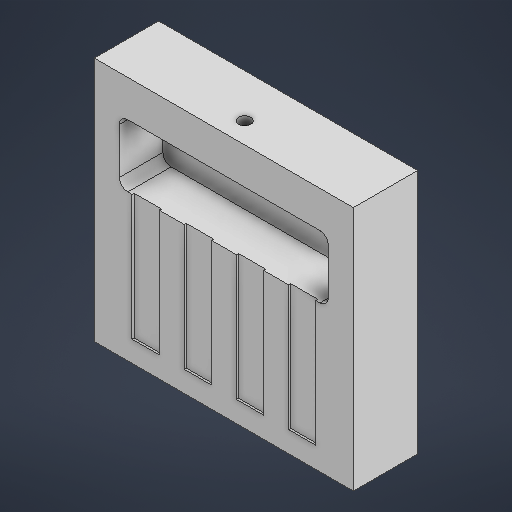
# Autodesk Inventor part: coffin_4Q_bottom
Saved by Autodesk Inventor 2026.2 (Build 302298010, 298A)
## iProperties
Created: 2026-11-02
Part Number: coffin_4Q_bottom
Material: Generic
Document SubType Name: Modeling
Designer: epm114
Mass: 47.8806 g
Surface Area: 125.077 cm^2
Volume: 47.8806 cm^3
Density: 1 g/cm^3
Appearance: Default
Author: epm114
Autodesk Inventor part; units mm, degrees
ref_plane "YZ Plane" through (0, 0, 0) normal (1, 0, 0) x (0, 1, 0)
ref_plane "XY Plane" through (0, 0, 0) normal (0, 0, 1) x (1, 0, 0)
sketch "Block_sketch" plane through (0, 0, 0) normal (0, 0, 1) x (1, 0, 0)
  line L0 (-31, -42.5) -> (31, -42.5)
  line L1 (31, -42.5) -> (31, 16.25)
  line L2 (31, 16.25) -> (-31, 16.25)
  line L3 (-31, 16.25) -> (-31, -42.5)
  point P0 (0, 0)
  dimension "d0" = 62
  dimension "d1" = 58.75
  dimension "d2" = 31
  dimension "d3" = 42.5
  constraints: 8 end point, 2 horizontal, 2 vertical
  measures "d0" distance between parallel lines of L3 L1
  measures "d1" distance between parallel lines of L0 L2
  measures "d2" horizontal distance of point (0, 0) L0.start
  measures "d3" vertical distance of point (0, 0) L0.start
extrude "Block" add sketch "Block_sketch" against normal blind 15.4
sketch "Cavity_sketch" plane through (0, 0, 0) normal (0, 0, 1) x (1, 0, 0)
  arc A0 (-25, -5.5) -> (-23, -7.5) centre (-23, -5.5) ccw
  arc A1 (23, -7.5) -> (25, -5.5) centre (23, -5.5) ccw
  arc A2 (25, 5.5) -> (23, 7.5) centre (23, 5.5) ccw
  arc A3 (-23, 7.5) -> (-25, 5.5) centre (-23, 5.5) ccw
  line L0 (-23, -7.5) -> (23, -7.5)
  line L1 (25, -5.5) -> (25, 5.5)
  line L2 (23, 7.5) -> (-23, 7.5)
  line L3 (-25, 5.5) -> (-25, -5.5)
  point P0 (0, 0)
  dimension "d6" = 50
  dimension "d7" = 15
  dimension "d8" = 2
  dimension "d9" = 2
  dimension "d10" = 2
  dimension "d11" = 2
  dimension "d12" = 23
  dimension "d13" = 5.5
  constraints: 8 end point, 8 point on circle, 8 tangent, 4 centre point, 2 horizontal, 2 vertical
  measures "d6" distance between parallel lines of L3 L1
  measures "d7" distance between parallel lines of L0 L2
  measures "d8" radius of A0
  measures "d9" radius of A1
  measures "d10" radius of A2
  measures "d11" radius of A3
  measures "d12" horizontal distance of point (0, 0) A0.centre
  measures "d13" vertical distance of point (0, 0) A0.centre
extrude "Cavity_pocket" cut sketch "Cavity_sketch" against normal blind 10.4
sketch "Chip_tunnels_sketch" plane through (0, 0, 0) normal (0, 0, 1) x (1, 0, 0)
  line L0 (-22, -37.5) -> (-15.5, -37.5)
  line L1 (-15.5, -37.5) -> (-15.5, -7)
  line L2 (-15.5, -7) -> (-22, -7)
  line L3 (-22, -7) -> (-22, -37.5)
  line L4 (-9.5, -37.5) -> (-3, -37.5)
  line L5 (-3, -37.5) -> (-3, -7)
  line L6 (-3, -7) -> (-9.5, -7)
  line L7 (-9.5, -7) -> (-9.5, -37.5)
  line L8 (3, -37.5) -> (9.5, -37.5)
  line L9 (9.5, -37.5) -> (9.5, -7)
  line L10 (9.5, -7) -> (3, -7)
  line L11 (3, -7) -> (3, -37.5)
  line L12 (15.5, -37.5) -> (22, -37.5)
  line L13 (22, -37.5) -> (22, -7)
  line L14 (22, -7) -> (15.5, -7)
  line L15 (15.5, -7) -> (15.5, -37.5)
  point P0 (0, 0)
  dimension "d16" = 6.5
  dimension "d17" = 30.5
  dimension "d18" = 22
  dimension "d19" = 37.5
  dimension "d20" = 6.5
  dimension "d21" = 30.5
  dimension "d22" = 9.5
  dimension "d23" = 37.5
  dimension "d24" = 6.5
  dimension "d25" = 30.5
  dimension "d26" = 3
  dimension "d27" = 37.5
  dimension "d28" = 6.5
  dimension "d29" = 30.5
  dimension "d30" = 15.5
  dimension "d31" = 37.5
  constraints: 32 end point, 8 horizontal, 8 vertical
  measures "d16" distance between parallel lines of L3 L1
  measures "d17" distance between parallel lines of L0 L2
  measures "d18" horizontal distance of point (0, 0) L0.start
  measures "d19" vertical distance of point (0, 0) L0.start
  measures "d20" distance between parallel lines of L7 L5
  measures "d21" distance between parallel lines of L4 L6
  measures "d22" horizontal distance of point (0, 0) L4.start
  measures "d23" vertical distance of point (0, 0) L4.start
  measures "d24" distance between parallel lines of L11 L9
  measures "d25" distance between parallel lines of L8 L10
  measures "d26" horizontal distance of point (0, 0) L8.start
  measures "d27" vertical distance of point (0, 0) L8.start
  measures "d28" distance between parallel lines of L15 L13
  measures "d29" distance between parallel lines of L12 L14
  measures "d30" horizontal distance of point (0, 0) L12.start
  measures "d31" vertical distance of point (0, 0) L12.start
extrude "Chip_tunnels" cut sketch "Chip_tunnels_sketch" against normal blind 0.5
ref_plane "RO_face_plane" through (0, 16.25, 0) normal (0, 1, 0) x (-1, 0, 0)
sketch "Readout_bores_sketch" plane through (0, 16.25, 0) normal (0, 1, 0) x (-1, 0, 0)
  circle A0 centre (0, -5) radius 1.473
  point P0 (0, 0)
  dimension "d35" = 2.946
  dimension "d36" = 5
  constraints: 1 centre point
  measures "d35" diameter of A0
  measures "d36" distance of point (0, 0) A0.centre
extrude "Readout_bores" cut sketch "Readout_bores_sketch" against normal blind 9.25
equation "\"d0\" = block_L"
equation "\"d1\" = y_back + y_front"
equation "\"d2\" = 0.5 * block_L"
equation "\"d3\" = y_back"
equation "\"d4\" = 0.5 * block_H"
equation "\"d6\" = cav_L"
equation "\"d7\" = cav_W"
equation "\"d8\" = cav_r"
equation "\"d9\" = cav_r"
equation "\"d10\" = cav_r"
equation "\"d11\" = cav_r"
equation "\"d12\" = -cav_r + 0.5 * cav_L"
equation "\"d13\" = -cav_r + 0.5 * cav_W"
equation "\"d14\" = 0.5 * cav_H"
equation "\"d16\" = tunnel_W"
equation "\"d17\" = tunnel_L + ovl"
equation "\"d18\" = 0.5 * tunnel_W - q1_x"
equation "\"d19\" = 0.5 * cav_W + tunnel_L"
equation "\"d20\" = tunnel_W"
equation "\"d21\" = tunnel_L + ovl"
equation "\"d22\" = 0.5 * tunnel_W - q2_x"
equation "\"d23\" = 0.5 * cav_W + tunnel_L"
equation "\"d24\" = tunnel_W"
equation "\"d25\" = tunnel_L + ovl"
equation "\"d26\" = q3_x - 0.5 * tunnel_W"
equation "\"d27\" = 0.5 * cav_W + tunnel_L"
equation "\"d28\" = tunnel_W"
equation "\"d29\" = tunnel_L + ovl"
equation "\"d30\" = q4_x - 0.5 * tunnel_W"
equation "\"d31\" = 0.5 * cav_W + tunnel_L"
equation "\"d32\" = chip_T"
equation "\"d35\" = ro_dia"
equation "\"d36\" = -ro1_z"
equation "\"d37\" = ro_port_len + ovl"
equation "\"cav_L\" = 50"
equation "\"cav_W\" = 15"
equation "\"cav_H\" = 20.8"
equation "\"cav_r\" = 2"
equation "\"wall_x\" = 6"
equation "\"wall_z\" = 5"
equation "\"wall_back\" = 5"
equation "\"chip_T\" = 0.5"
equation "\"tunnel_W\" = 6.5"
equation "\"tunnel_L\" = 30"
equation "\"tunnel_r\" = 0"
equation "\"q1_x\" = -0.375 * cav_L"
equation "\"q2_x\" = -0.125 * cav_L"
equation "\"q3_x\" = 0.125 * cav_L"
equation "\"q4_x\" = 0.375 * cav_L"
equation "\"top_pocket_D\" = 0.43"
equation "\"drive_dia\" = 2.946"
equation "\"drive_dy\" = 7.5"
equation "\"ro_dia\" = 2.946"
equation "\"ro_port_len\" = 8.75"
equation "\"ro1_x\" = 0"
equation "\"ro1_z\" = -5"
equation "\"ro2_x\" = 0"
equation "\"ro2_z\" = 5"
equation "\"ovl\" = 0.5"
equation "\"block_L\" = cav_L + 2 * wall_x"
equation "\"block_H\" = cav_H + 2 * wall_z"
equation "\"y_front\" = 0.5 * cav_W + ro_port_len"
equation "\"y_back\" = tunnel_L + 0.5 * cav_W + wall_back"
equation "\"d34\" = y_front"
body "Solid1"
